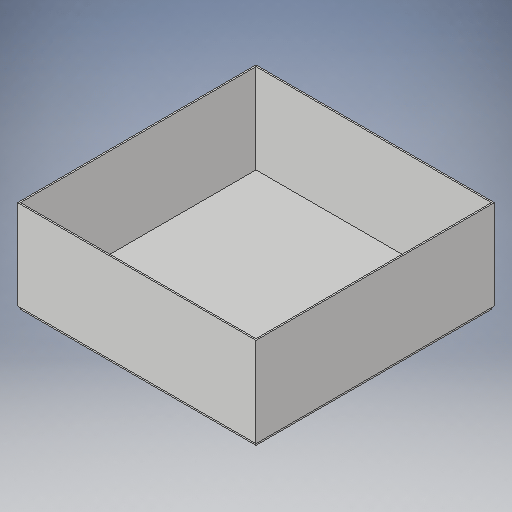
# Autodesk Inventor part: BT028_thutrn22_26
Saved by Autodesk Inventor 2025.3 (Build 293356000, 356)
## iProperties
Company: HTBLA Kaindorf
RuleStatus: InUse
Created: 2026-08-21
Part Number: BT028_thutrn22_26
Project: Biegeroboter
Material: Generisch
Description: gehaeuse_display
Document SubType Name: Modeling
Designer: thutrn22
Density: 1 g/cm^3
Appearance: Vorgabe
Mass: 11011 g
Surface Area: 32196 cm^2
Volume: 11011 cm^3
AfterDocNew0: iProperties-Editor_aufrufen
Author: trist
Keywords: 2026
Autodesk Inventor part; units mm, degrees
ref_plane "YZ Plane" through (0, 0, 0) normal (1, 0, 0) x (0, 1, 0)
ref_plane "XZ Plane" through (0, 0, 0) normal (0, 1, 0) x (-1, 0, 0)
ref_plane "XY Plane" through (0, 0, 0) normal (0, 0, 1) x (1, 0, 0)
sketch "Skizze3" plane through (0, 0, 0) normal (0, 0, 1) x (1, 0, 0)
  line L0 (-400, 400) -> (400, 400)
  line L1 (400, 400) -> (400, -400)
  line L2 (400, -400) -> (-400, -400)
  line L3 (-400, -400) -> (-400, 400)
  line L4 (0, -560) -> (0, 560) projected
  line L5 (-560, 0) -> (560, 0) projected
  line L6 (-395, 395) -> (395, 395)
  line L7 (395, 395) -> (395, -395)
  line L8 (395, -395) -> (-395, -395)
  line L9 (-395, -395) -> (-395, 395)
  point P0 (0, 0)
  dimension "d4" = 800
  dimension "d5" = 800
  dimension "d6" = 790
  dimension "d7" = 790
  constraints: 16 end point, 4 parallel, 2 horizontal, 2 perpendicular, 4 other
  measures "d4" distance of L1.end L2.end
  measures "d5" distance of L0.end L1.end
  measures "d6" distance of L7.end L8.end
  measures "d7" distance of L6.end L7.end
extrude "Extrusion3" add sketch "Skizze3" along normal blind 10 contours L6 L7 L5 L4 | L4 L5 L9 L6 | L5 L4 L8 L9 | L5 L7 L8 L4
sketch "Skizze4" plane through (0, 0, 10) normal (0, 0, 1) x (1, 0, 0)
  line L0 (-400, 400) -> (400, 400)
  line L1 (400, 400) -> (400, -400)
  line L2 (400, -400) -> (-400, -400)
  line L3 (-400, -400) -> (-400, 400)
  line L4 (0, -560) -> (0, 560) projected
  line L5 (-560, 0) -> (560, 0) projected
  line L6 (-395, 395) -> (-395, -395) projected
  line L7 (-395, 395) -> (395, 395)
  line L8 (395, 395) -> (395, -395)
  line L9 (395, -395) -> (-395, -395)
  line L10 (-395, -395) -> (-395, 395)
  point P0 (0, 0)
  dimension "d10" = 800
  dimension "d11" = 800
  dimension "d12" = 790
  dimension "d13" = 790
  constraints: 16 end point, 4 parallel, 2 horizontal, 2 perpendicular, 2 other
  measures "d10" distance of L1.end L2.end
  measures "d11" distance of L0.end L1.end
  measures "d12" distance of L8.end L9.end
  measures "d13" distance of L7.end L8.end
extrude "Extrusion4" add sketch "Skizze4" along normal blind 300 contours L0 L4 L7 L6 L5 L3 | L0 L1 L5 L8 L7 L4 | L5 L6 L9 L4 L2 L3 | L1 L2 L4 L9 L8 L5
